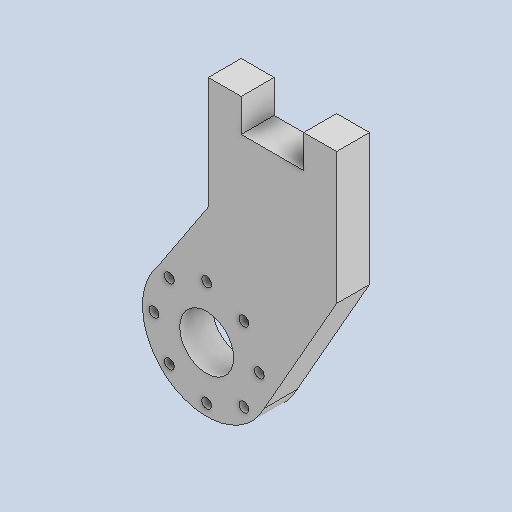
# Autodesk Inventor part: ElbowSide
Saved by Autodesk Inventor 2025.2 (Build 292293000, 293)
## iProperties
Created: 2025-06-27
Part Number: ElbowSide
Material: Generic
Document SubType Name: Modeling
Designer: ricoa
Density: 1 g/cm^3
Appearance: Default
Author: ricoa
Autodesk Inventor part; units mm, degrees
ref_plane "YZ Plane" through (0, 0, 0) normal (1, 0, 0) x (0, 1, 0)
ref_plane "XZ Plane" through (0, 0, 0) normal (0, 1, 0) x (-1, 0, 0)
ref_plane "XY Plane" through (0, 0, 0) normal (0, 0, 1) x (1, 0, 0)
sketch "Sketch1" plane through (0, 0, 0) normal (0, 0, 1) x (1, 0, 0)
  line L0 (-9.75, 40) -> (-9.75, 35)
  line L1 (-9.75, 35) -> (-4.75, 35)
  line L2 (-4.75, 35) -> (-4.75, 30)
  line L3 (9.75, 35) -> (4.75, 35)
  line L4 (4.75, 35) -> (4.75, 30)
  line L5 (4.75, 30) -> (-4.75, 30)
  line L6 (-10, 0) -> (-10, 30) construction
  line L7 (-10, 30) -> (0, 30) construction
  circle A0 centre (-10, 0) radius 4.1
  line L8 (-10, 0) -> (-18, 0) construction
  circle A1 centre (-18, 0) radius 0.75
  circle A2 centre (-15.6569, -5.6569) radius 0.75
  circle A3 centre (-10, -8) radius 0.75
  circle A4 centre (-4.3431, -5.6569) radius 0.75
  circle A5 centre (-2, 0) radius 0.75
  circle A6 centre (-4.3431, 5.6569) radius 0.75
  circle A7 centre (-10, 8) radius 0.75
  circle A8 centre (-15.6569, 5.6569) radius 0.75
  arc A9 (-17.3986, 6.35) -> (-1.25, -4.3012) centre (-10, 0) ccw
  line L9 (9.75, 35) -> (9.75, 30)
  line L10 (9.75, 30) -> (9.75, 15)
  line L11 (9.75, 15) -> (-1.25, -4.3012)
  line L12 (-1.25, -4.3012) -> (-17.3986, 6.35) construction
  line L13 (-17.3986, 6.35) -> (-9.75, 17.9464)
  line L14 (-9.75, 17.9464) -> (-9.75, 35)
  dimension "d3" = 5
  dimension "d4" = 5
  dimension "d7" = 5
  dimension "d8" = 5
  dimension "d11" = 8
  dimension "d12" = 1.5
  dimension "d13" = 10
  dimension "d14" = 30
  dimension "d17" = 360
  dimension "d19" = 19.5
  dimension "d20" = 15
  constraints: 30 end point, 10 centre point, 5 perpendicular, 3 coincident, 2 horizontal, 2 point on circle, 2 vertical, 1 midpoint, 1 parallel, 1 point on line, 17 other
  measures "d3" distance of L0.end L1.end
  measures "d4" distance of L3.start L3.end
  measures "d7" distance between parallel lines of L5 L1
  measures "d8" distance between parallel lines of L5 L3
  measures "d11" distance of L8.start L8.end
  measures "d12" diameter of A1
  measures "d13" distance of L6.end L7.end
  measures "d14" distance of L6.start L6.end
  measures "d19" diameter of A9
  measures "d20" distance of L9.end L10.end
extrude "Extrusion1" add sketch "Sketch1" along normal blind 5
body "Solid1"
